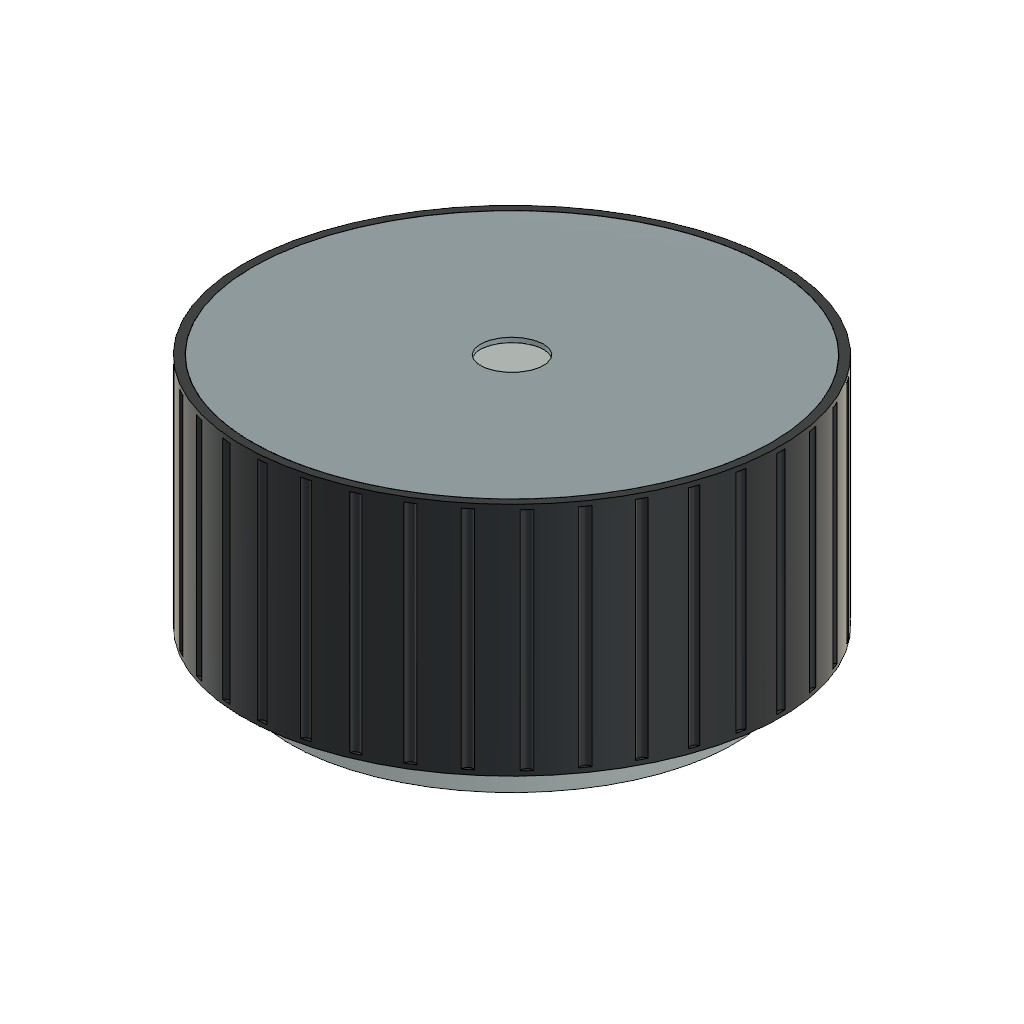
HW17-R0-Fusion (Autodesk Fusion 360 design; units mm, degrees)
description: 12-slot / 14-pole custom brushless haptic wheel. Rotation only. Native Fusion reconstruction of 2026-10-24 R0; concept/prototype, not manufacturing release.
part number: 2026-10-29-11-14-16-184
part number: 2026-10-29-11-14-16-256
part number: 2026-10-29-11-14-16-259
description: POM | 36 shallow axial flutes, max OD17; black matte finish
part number: HW17-R0-01_grip_ring
description: low-carbon magnetic steel; supplier B-H curve required | OD16.4 ID15.4; 0.50 radial wall
part number: HW17-R0-02_rotor_back_iron
description: 6061-T6 aluminium | Spigot adhesive joint; shaft hub controls inner-ring spacing. Final fits by bearing supplier.
part number: HW17-R0-03_rotor_cap
description: Nonmagnetic austenitic stainless steel | D2 precision ground seats; integral lower D2.6 thrust collar, magnet bond face
part number: HW17-R0-04_rotor_shaft
description: N35SH sintered NdFeB, 14 custom radially magnetized arc segments; alternate inward N/S; epoxy protective coating | Pole label is the inward-facing surface; 0.6 degree adhesive joint; independent arcs form a 14-pole ring
part number: HW17-R0-05_magnet_01_N
part number: HW17-R0-05_magnet_02_S
part number: HW17-R0-05_magnet_03_N
part number: HW17-R0-05_magnet_04_S
part number: HW17-R0-05_magnet_05_N
part number: HW17-R0-05_magnet_06_S
part number: HW17-R0-05_magnet_07_N
part number: HW17-R0-05_magnet_08_S
part number: HW17-R0-05_magnet_09_N
part number: HW17-R0-05_magnet_10_S
part number: HW17-R0-05_magnet_11_N
part number: HW17-R0-05_magnet_12_S
part number: HW17-R0-05_magnet_13_N
part number: HW17-R0-05_magnet_14_S
description: 6061-T6 aluminium | Three M1.4 blind pilot holes, bearing fits and adhesive retention require tolerance review
part number: HW17-R0-06_stator_carrier
description: 0.20 mm insulated non-oriented electrical steel, supplier to provide B-H and loss curves | 20 nominal 0.20 mm insulated laminations; final assembled stack 4.00 mm incl. coating
part number: HW17-R0-07_stator_stack
description: Enamelled copper winding envelope | A+, 32 turns D0.13 Cu, finished OD <=0.145, 11/11/10 layers. Envelope is not solid copper.
part number: HW17-R0-08_coil_01_Ap
description: Enamelled copper winding envelope | A-, 32 turns D0.13 Cu, finished OD <=0.145, 11/11/10 layers. Envelope is not solid copper.
part number: HW17-R0-08_coil_02_An
description: Enamelled copper winding envelope | B-, 32 turns D0.13 Cu, finished OD <=0.145, 11/11/10 layers. Envelope is not solid copper.
part number: HW17-R0-08_coil_03_Bn
description: Enamelled copper winding envelope | B+, 32 turns D0.13 Cu, finished OD <=0.145, 11/11/10 layers. Envelope is not solid copper.
part number: HW17-R0-08_coil_04_Bp
description: Enamelled copper winding envelope | C+, 32 turns D0.13 Cu, finished OD <=0.145, 11/11/10 layers. Envelope is not solid copper.
part number: HW17-R0-08_coil_05_Cp
description: Enamelled copper winding envelope | C-, 32 turns D0.13 Cu, finished OD <=0.145, 11/11/10 layers. Envelope is not solid copper.
part number: HW17-R0-08_coil_06_Cn
part number: HW17-R0-08_coil_07_An
part number: HW17-R0-08_coil_08_Ap
part number: HW17-R0-08_coil_09_Bp
part number: HW17-R0-08_coil_10_Bn
part number: HW17-R0-08_coil_11_Cn
part number: HW17-R0-08_coil_12_Cp
description: EZO MR52ZZ 2 x 5 x 2.5 | Envelope only, rolling elements not modelled; zero interference fit in nominal geometry
part number: HW17-R0-09_bearing_1
part number: HW17-R0-09_bearing_2
description: Ground nonmagnetic stainless shim | Match inner/outer spacing to avoid unintended preload; select shim after measurement
part number: HW17-R0-10_inner_spacer
description: Nonmagnetic stainless steel | Bonded outer-race retainer; no contact with inner ring or shields outside outer-ring land
part number: HW17-R0-11_lower_outer_retainer
part number: HW17-R0-12_upper_outer_retainer
description: NdFeB, diametrically magnetized | Single pole pair; D4 x 0.5; 0.02 adhesive to shaft collar. Non-reference magnet requires field validation.
part number: HW17-R0-13_sensor_magnet
description: Rigid-flex envelope, 0.4 mm central stiffened island | D5.5 sensor island and 1.6 mm tail to module edge; actual PCB layout not included
part number: HW17-R0-14_sensor_flex
description: MT6701QT-STD QFN16 | Maximum 3.1 x 3.1 x 0.8 body plus 0.05 solder allowance
part number: HW17-R0-15_MT6701_max_envelope
description: 0201 capacitor envelope | 100 nF adjacent VDD/GND; land pattern and routing to be designed
part number: HW17-R0-16_sensor_decoupling
Autodesk Fusion 360 part; units mm, degrees
(part 1 of 2)
sketch "Sketch1" plane through (0, 0, 0) normal (0, 0, 1) x (1, 0, 0) in component "01_grip_ring POM 防滑外圈"
  circle A0 centre (0, 0) radius 8.5
  circle A1 centre (0, 0) radius 8.2
  dimension "d50" = 17
  dimension "d51" = 16.4
  measures "d50" diameter of A0
  measures "d51" diameter of A1
extrude "外圈 OD17 ID16.4" add sketch "Sketch1" along normal blind 7.6 from surface at 1.2 makes body 1 in component "01_grip_ring POM 防滑外圈"
sketch "Sketch2" plane through (0, 0, 0) normal (0, 0, 1) x (1, 0, 0) in component "01_grip_ring POM 防滑外圈"
  circle A0 centre (8.56, 0) radius 0.18
  circle A1 centre (8.43, 1.4864) radius 0.18
  circle A2 centre (8.0438, 2.9277) radius 0.18
  circle A3 centre (7.4132, 4.28) radius 0.18
  circle A4 centre (6.5573, 5.5023) radius 0.18
  circle A5 centre (5.5023, 6.5573) radius 0.18
  circle A6 centre (4.28, 7.4132) radius 0.18
  circle A7 centre (2.9277, 8.0438) radius 0.18
  circle A8 centre (1.4864, 8.43) radius 0.18
  circle A9 centre (0, 8.56) radius 0.18
  circle A10 centre (-1.4864, 8.43) radius 0.18
  circle A11 centre (-2.9277, 8.0438) radius 0.18
  circle A12 centre (-4.28, 7.4132) radius 0.18
  circle A13 centre (-5.5023, 6.5573) radius 0.18
  circle A14 centre (-6.5573, 5.5023) radius 0.18
  circle A15 centre (-7.4132, 4.28) radius 0.18
  circle A16 centre (-8.0438, 2.9277) radius 0.18
  circle A17 centre (-8.43, 1.4864) radius 0.18
  circle A18 centre (-8.56, 0) radius 0.18
  circle A19 centre (-8.43, -1.4864) radius 0.18
  circle A20 centre (-8.0438, -2.9277) radius 0.18
  circle A21 centre (-7.4132, -4.28) radius 0.18
  circle A22 centre (-6.5573, -5.5023) radius 0.18
  circle A23 centre (-5.5023, -6.5573) radius 0.18
  circle A24 centre (-4.28, -7.4132) radius 0.18
  circle A25 centre (-2.9277, -8.0438) radius 0.18
  circle A26 centre (-1.4864, -8.43) radius 0.18
  circle A27 centre (0, -8.56) radius 0.18
  circle A28 centre (1.4864, -8.43) radius 0.18
  circle A29 centre (2.9277, -8.0438) radius 0.18
  circle A30 centre (4.28, -7.4132) radius 0.18
  circle A31 centre (5.5023, -6.5573) radius 0.18
  circle A32 centre (6.5573, -5.5023) radius 0.18
  circle A33 centre (7.4132, -4.28) radius 0.18
  circle A34 centre (8.0438, -2.9277) radius 0.18
  circle A35 centre (8.43, -1.4864) radius 0.18
extrude "轴向防滑槽 36x" cut sketch "Sketch2" along normal blind 7.3 from surface at 1.35 bodies 1 in component "01_grip_ring POM 防滑外圈"
sketch "Sketch1 (2)" plane through (0, 0, 0) normal (0, 0, 1) x (1, 0, 0) in component "02_rotor_back_iron 低碳钢磁轭"
  circle A0 centre (0, 0) radius 8.2
  circle A1 centre (0, 0) radius 7.7
  dimension "d58" = 16.4
  dimension "d59" = 15.4
  measures "d58" diameter of A0
  measures "d59" diameter of A1
extrude "磁轭 0.50mm 径向壁厚" add sketch "Sketch1 (2)" along normal blind 6.8 from surface at 1.2 separate body makes body 2 in component "02_rotor_back_iron 低碳钢磁轭"
sketch "Sketch1 (3)" plane through (0, 0, 0) normal (0, 0, 1) x (1, 0, 0) in component "03_rotor_cap 铝端盖"
  circle A0 centre (0, 0) radius 8.2
  circle A1 centre (0, 0) radius 1
  dimension "d63" = 16.4
  dimension "d64" = 2
  measures "d63" diameter of A0
  measures "d64" diameter of A1
extrude "端盖" add sketch "Sketch1 (3)" along normal blind 0.8 from surface at 8 separate body makes body 3 in component "03_rotor_cap 铝端盖"
sketch "Sketch2 (2)" plane through (0, 0, 0) normal (0, 0, 1) x (1, 0, 0) in component "03_rotor_cap 铝端盖"
  circle A0 centre (0, 0) radius 7.68
  circle A1 centre (0, 0) radius 7
  dimension "d68" = 15.36
  dimension "d69" = 14
  measures "d68" diameter of A0
  measures "d69" diameter of A1
extrude "胶接定位止口" add sketch "Sketch2 (2)" along normal blind 0.6 from surface at 7.4 bodies 3 in component "03_rotor_cap 铝端盖"
sketch "Sketch3" plane through (0, 0, 0) normal (0, 0, 1) x (1, 0, 0) in component "03_rotor_cap 铝端盖"
  circle A0 centre (0, 0) radius 1.3
  circle A1 centre (0, 0) radius 1
  dimension "d73" = 2.6
  dimension "d74" = 2
  measures "d73" diameter of A0
  measures "d74" diameter of A1
extrude "轴承内圈压肩" add sketch "Sketch3" along normal blind 0.2 from surface at 7.8 bodies 3 in component "03_rotor_cap 铝端盖"
sketch "Sketch4" plane through (0, 0, 0) normal (0, 0, 1) x (1, 0, 0) in component "03_rotor_cap 铝端盖"
  circle A0 centre (0, 0) radius 3.2
  circle A1 centre (0, 0) radius 1.4
extrude "上挡环避让" cut sketch "Sketch4" along normal blind 0.31 from surface at 7.79 bodies 3 in component "03_rotor_cap 铝端盖"
sketch "Sketch1 (4)" plane through (0, 0, 0) normal (0, 0, 1) x (1, 0, 0) in component "04_rotor_shaft 非磁性精密轴 D2"
  circle A0 centre (0, 0) radius 1
  dimension "d81" = 2
  measures "d81" diameter of A0
extrude "轴身" add sketch "Sketch1 (4)" along normal blind 5.95 from surface at 2.7 separate body makes body 4 in component "04_rotor_shaft 非磁性精密轴 D2"
sketch "Sketch2 (3)" plane through (0, 0, 0) normal (0, 0, 1) x (1, 0, 0) in component "04_rotor_shaft 非磁性精密轴 D2"
  circle A0 centre (0, 0) radius 1.3
  dimension "d85" = 2.6
  measures "d85" diameter of A0
extrude "轴底肩" add sketch "Sketch2 (3)" along normal blind 0.3 from surface at 2.4 bodies 4 in component "04_rotor_shaft 非磁性精密轴 D2"
sketch "Sketch1 (5)" plane through (0, 0, 0) normal (0, 0, 1) x (1, 0, 0) in component "05_magnet_01_N 弧形磁钢 内侧N极"
  arc A0 (7.467, -1.6632) -> (7.467, 1.6632) centre (0, 0) ccw
  arc A1 (6.5885, -1.4675) -> (6.5885, 1.4675) centre (0, 0) ccw
  line L0 (7.467, -1.6632) -> (6.5885, -1.4675)
  line L1 (7.467, 1.6632) -> (6.5885, 1.4675)
extrude "径向充磁 N35SH" add sketch "Sketch1 (5)" along normal blind 4.5 from surface at 2.05 separate body makes body 5 in component "05_magnet_01_N 弧形磁钢 内侧N极"
sketch "Sketch1 (6)" plane through (0, 0, 0) normal (0, 0, 1) x (1, 0, 0) in component "05_magnet_02_S 弧形磁钢 内侧S极"
  arc A0 (7.4492, 1.7413) -> (6.0059, 4.7383) centre (0, 0) ccw
  arc A1 (6.5728, 1.5365) -> (5.2993, 4.1809) centre (0, 0) ccw
  line L0 (7.4492, 1.7413) -> (6.5728, 1.5365)
  line L1 (6.0059, 4.7383) -> (5.2993, 4.1809)
extrude "径向充磁 N35SH'" add sketch "Sketch1 (6)" along normal blind 4.5 from surface at 2.05 separate body makes body 6 in component "05_magnet_02_S 弧形磁钢 内侧S极"
sketch "Sketch1 (7)" plane through (0, 0, 0) normal (0, 0, 1) x (1, 0, 0) in component "05_magnet_03_N 弧形磁钢 内侧N极"
  arc A0 (5.956, 4.8009) -> (3.3553, 6.8749) centre (0, 0) ccw
  arc A1 (5.2553, 4.2361) -> (2.9605, 6.0661) centre (0, 0) ccw
  line L0 (5.956, 4.8009) -> (5.2553, 4.2361)
  line L1 (3.3553, 6.8749) -> (2.9605, 6.0661)
extrude "径向充磁 N35SH''" add sketch "Sketch1 (7)" along normal blind 4.5 from surface at 2.05 separate body makes body 7 in component "05_magnet_03_N 弧形磁钢 内侧N极"
sketch "Sketch1 (8)" plane through (0, 0, 0) normal (0, 0, 1) x (1, 0, 0) in component "05_magnet_04_S 弧形磁钢 内侧S极"
  arc A0 (3.2831, 6.9097) -> (0.0401, 7.6499) centre (0, 0) ccw
  arc A1 (2.8968, 6.0968) -> (0.0353, 6.7499) centre (0, 0) ccw
  line L0 (3.2831, 6.9097) -> (2.8968, 6.0968)
  line L1 (0.0401, 7.6499) -> (0.0353, 6.7499)
extrude "径向充磁 N35SH'''" add sketch "Sketch1 (8)" along normal blind 4.5 from surface at 2.05 separate body makes body 8 in component "05_magnet_04_S 弧形磁钢 内侧S极"
sketch "Sketch1 (9)" plane through (0, 0, 0) normal (0, 0, 1) x (1, 0, 0) in component "05_magnet_05_N 弧形磁钢 内侧N极"
  arc A0 (-0.0401, 7.6499) -> (-3.2831, 6.9097) centre (0, 0) ccw
  arc A1 (-0.0353, 6.7499) -> (-2.8968, 6.0968) centre (0, 0) ccw
  line L0 (-0.0401, 7.6499) -> (-0.0353, 6.7499)
  line L1 (-3.2831, 6.9097) -> (-2.8968, 6.0968)
extrude "径向充磁 N35SH''''" add sketch "Sketch1 (9)" along normal blind 4.5 from surface at 2.05 separate body makes body 9 in component "05_magnet_05_N 弧形磁钢 内侧N极"
sketch "Sketch1 (10)" plane through (0, 0, 0) normal (0, 0, 1) x (1, 0, 0) in component "05_magnet_06_S 弧形磁钢 内侧S极"
  arc A0 (-3.3553, 6.8749) -> (-5.956, 4.8009) centre (0, 0) ccw
  arc A1 (-2.9605, 6.0661) -> (-5.2553, 4.2361) centre (0, 0) ccw
  line L0 (-3.3553, 6.8749) -> (-2.9605, 6.0661)
  line L1 (-5.956, 4.8009) -> (-5.2553, 4.2361)
extrude "径向充磁 N35SH'''''" add sketch "Sketch1 (10)" along normal blind 4.5 from surface at 2.05 separate body makes body 10 in component "05_magnet_06_S 弧形磁钢 内侧S极"
sketch "Sketch1 (11)" plane through (0, 0, 0) normal (0, 0, 1) x (1, 0, 0) in component "05_magnet_07_N 弧形磁钢 内侧N极"
  arc A0 (-6.0059, 4.7383) -> (-7.4492, 1.7413) centre (0, 0) ccw
  arc A1 (-5.2993, 4.1809) -> (-6.5728, 1.5365) centre (0, 0) ccw
  line L0 (-6.0059, 4.7383) -> (-5.2993, 4.1809)
  line L1 (-7.4492, 1.7413) -> (-6.5728, 1.5365)
extrude "径向充磁 N35SH''''''" add sketch "Sketch1 (11)" along normal blind 4.5 from surface at 2.05 separate body makes body 11 in component "05_magnet_07_N 弧形磁钢 内侧N极"
sketch "Sketch1 (12)" plane through (0, 0, 0) normal (0, 0, 1) x (1, 0, 0) in component "05_magnet_08_S 弧形磁钢 内侧S极"
  arc A0 (-7.467, 1.6632) -> (-7.467, -1.6632) centre (0, 0) ccw
  arc A1 (-6.5885, 1.4675) -> (-6.5885, -1.4675) centre (0, 0) ccw
  line L0 (-7.467, 1.6632) -> (-6.5885, 1.4675)
  line L1 (-7.467, -1.6632) -> (-6.5885, -1.4675)
extrude "径向充磁 N35SH'''''''" add sketch "Sketch1 (12)" along normal blind 4.5 from surface at 2.05 separate body makes body 12 in component "05_magnet_08_S 弧形磁钢 内侧S极"
sketch "Sketch1 (13)" plane through (0, 0, 0) normal (0, 0, 1) x (1, 0, 0) in component "05_magnet_09_N 弧形磁钢 内侧N极"
  arc A0 (-7.4492, -1.7413) -> (-6.0059, -4.7383) centre (0, 0) ccw
  arc A1 (-6.5728, -1.5365) -> (-5.2993, -4.1809) centre (0, 0) ccw
  line L0 (-7.4492, -1.7413) -> (-6.5728, -1.5365)
  line L1 (-6.0059, -4.7383) -> (-5.2993, -4.1809)
extrude "径向充磁 N35SH''''''''" add sketch "Sketch1 (13)" along normal blind 4.5 from surface at 2.05 separate body makes body 13 in component "05_magnet_09_N 弧形磁钢 内侧N极"
sketch "Sketch1 (14)" plane through (0, 0, 0) normal (0, 0, 1) x (1, 0, 0) in component "05_magnet_10_S 弧形磁钢 内侧S极"
  arc A0 (-5.956, -4.8009) -> (-3.3553, -6.8749) centre (0, 0) ccw
  arc A1 (-5.2553, -4.2361) -> (-2.9605, -6.0661) centre (0, 0) ccw
  line L0 (-5.956, -4.8009) -> (-5.2553, -4.2361)
  line L1 (-3.3553, -6.8749) -> (-2.9605, -6.0661)
extrude "径向充磁 N35SH'''''''''" add sketch "Sketch1 (14)" along normal blind 4.5 from surface at 2.05 separate body makes body 14 in component "05_magnet_10_S 弧形磁钢 内侧S极"
sketch "Sketch1 (15)" plane through (0, 0, 0) normal (0, 0, 1) x (1, 0, 0) in component "05_magnet_11_N 弧形磁钢 内侧N极"
  arc A0 (-3.2831, -6.9097) -> (-0.0401, -7.6499) centre (0, 0) ccw
  arc A1 (-2.8968, -6.0968) -> (-0.0353, -6.7499) centre (0, 0) ccw
  line L0 (-3.2831, -6.9097) -> (-2.8968, -6.0968)
  line L1 (-0.0401, -7.6499) -> (-0.0353, -6.7499)
extrude "径向充磁 N35SH''''''''''" add sketch "Sketch1 (15)" along normal blind 4.5 from surface at 2.05 separate body makes body 15 in component "05_magnet_11_N 弧形磁钢 内侧N极"
sketch "Sketch1 (16)" plane through (0, 0, 0) normal (0, 0, 1) x (1, 0, 0) in component "05_magnet_12_S 弧形磁钢 内侧S极"
  arc A0 (0.0401, -7.6499) -> (3.2831, -6.9097) centre (0, 0) ccw
  arc A1 (0.0353, -6.7499) -> (2.8968, -6.0968) centre (0, 0) ccw
  line L0 (0.0401, -7.6499) -> (0.0353, -6.7499)
  line L1 (3.2831, -6.9097) -> (2.8968, -6.0968)
extrude "径向充磁 N35SH'''''''''''" add sketch "Sketch1 (16)" along normal blind 4.5 from surface at 2.05 separate body makes body 16 in component "05_magnet_12_S 弧形磁钢 内侧S极"
sketch "Sketch1 (17)" plane through (0, 0, 0) normal (0, 0, 1) x (1, 0, 0) in component "05_magnet_13_N 弧形磁钢 内侧N极"
  arc A0 (3.3553, -6.8749) -> (5.956, -4.8009) centre (0, 0) ccw
  arc A1 (2.9605, -6.0661) -> (5.2553, -4.2361) centre (0, 0) ccw
  line L0 (3.3553, -6.8749) -> (2.9605, -6.0661)
  line L1 (5.956, -4.8009) -> (5.2553, -4.2361)
extrude "径向充磁 N35SH''''''''''''" add sketch "Sketch1 (17)" along normal blind 4.5 from surface at 2.05 separate body makes body 17 in component "05_magnet_13_N 弧形磁钢 内侧N极"
sketch "Sketch1 (18)" plane through (0, 0, 0) normal (0, 0, 1) x (1, 0, 0) in component "05_magnet_14_S 弧形磁钢 内侧S极"
  arc A0 (6.0059, -4.7383) -> (7.4492, -1.7413) centre (0, 0) ccw
  arc A1 (5.2993, -4.1809) -> (6.5728, -1.5365) centre (0, 0) ccw
  line L0 (6.0059, -4.7383) -> (5.2993, -4.1809)
  line L1 (7.4492, -1.7413) -> (6.5728, -1.5365)
extrude "径向充磁 N35SH'''''''''''''" add sketch "Sketch1 (18)" along normal blind 4.5 from surface at 2.05 separate body makes body 18 in component "05_magnet_14_S 弧形磁钢 内侧S极"
sketch "Sketch1 (19)" plane through (0, 0, 0) normal (0, 0, 1) x (1, 0, 0) in component "06_stator_carrier 铝固定座"
  circle A0 centre (0, 0) radius 7
  dimension "d131" = 14
  measures "d131" diameter of A0
extrude "安装底盘" add sketch "Sketch1 (19)" along normal blind 0.6 separate body makes body 19 in component "06_stator_carrier 铝固定座"
sketch "Sketch2 (4)" plane through (0, 0, 0) normal (0, 0, 1) x (1, 0, 0) in component "06_stator_carrier 铝固定座"
  circle A0 centre (0, 0) radius 2.8
  dimension "d135" = 5.6
  measures "d135" diameter of A0
extrude "传感器板沉腔" cut sketch "Sketch2 (4)" along normal blind 0.41 from surface at -0.01 bodies 19 in component "06_stator_carrier 铝固定座"
sketch "Sketch3 (2)" plane through (0, 0, 0) normal (0, 0, 1) x (1, 0, 0) in component "06_stator_carrier 铝固定座"
  circle A0 centre (0, 0) radius 2.5
  dimension "d139" = 5
  measures "d139" diameter of A0
extrude "中心通腔" cut sketch "Sketch3 (2)" along normal blind 0.21 from surface at 0.4 bodies 19 in component "06_stator_carrier 铝固定座"
sketch "Sketch4 (2)" plane through (0, 0, 0) normal (0, 0, 1) x (1, 0, 0) in component "06_stator_carrier 铝固定座"
  circle A0 centre (0, 0) radius 3
  circle A1 centre (0, 0) radius 2.5
  dimension "d143" = 6
  dimension "d144" = 5
  measures "d143" diameter of A0
  measures "d144" diameter of A1
extrude "轴承座筒" add sketch "Sketch4 (2)" along normal blind 7.2 from surface at 0.6 bodies 19 in component "06_stator_carrier 铝固定座"
sketch "Sketch5" plane through (0, 0, 0) normal (0, 0, 1) x (1, 0, 0) in component "06_stator_carrier 铝固定座"
  circle A0 centre (0, 0) radius 2.5
  circle A1 centre (0, 0) radius 2.25
  dimension "d148" = 5
  dimension "d149" = 4.5
  measures "d148" diameter of A0
  measures "d149" diameter of A1
extrude "轴承外圈间隔肩" add sketch "Sketch5" along normal blind 0.1 from surface at 5.2 bodies 19 in component "06_stator_carrier 铝固定座"
sketch "Sketch6" plane through (0, 0, 0) normal (0, 0, 1) x (1, 0, 0) in component "06_stator_carrier 铝固定座"
  circle A0 centre (4.6765, 2.7) radius 1.2
  dimension "d153" = 2.4
  measures "d153" diameter of A0
extrude "安装凸台 1" add sketch "Sketch6" along normal blind 0.9 from surface at 0.6 bodies 19 in component "06_stator_carrier 铝固定座"
sketch "Sketch7" plane through (0, 0, 0) normal (0, 0, 1) x (1, 0, 0) in component "06_stator_carrier 铝固定座"
  circle A0 centre (4.6765, 2.7) radius 0.55
  dimension "d157" = 1.1
  measures "d157" diameter of A0
extrude "M1.4 底孔 1 无牙型" cut sketch "Sketch7" along normal blind 1.26 from surface at -0.01 bodies 19 in component "06_stator_carrier 铝固定座"
sketch "Sketch8" plane through (0, 0, 0) normal (0, 0, 1) x (1, 0, 0) in component "06_stator_carrier 铝固定座"
  circle A0 centre (-4.6765, 2.7) radius 1.2
  dimension "d161" = 2.4
  measures "d161" diameter of A0
extrude "安装凸台 2" add sketch "Sketch8" along normal blind 0.9 from surface at 0.6 bodies 19 in component "06_stator_carrier 铝固定座"
sketch "Sketch9" plane through (0, 0, 0) normal (0, 0, 1) x (1, 0, 0) in component "06_stator_carrier 铝固定座"
  circle A0 centre (-4.6765, 2.7) radius 0.55
  dimension "d165" = 1.1
  measures "d165" diameter of A0
extrude "M1.4 底孔 2 无牙型" cut sketch "Sketch9" along normal blind 1.26 from surface at -0.01 bodies 19 in component "06_stator_carrier 铝固定座"
sketch "Sketch10" plane through (0, 0, 0) normal (0, 0, 1) x (1, 0, 0) in component "06_stator_carrier 铝固定座"
  circle A0 centre (0, -5.4) radius 1.2
  dimension "d169" = 2.4
  measures "d169" diameter of A0
extrude "安装凸台 3" add sketch "Sketch10" along normal blind 0.9 from surface at 0.6 bodies 19 in component "06_stator_carrier 铝固定座"
sketch "Sketch11" plane through (0, 0, 0) normal (0, 0, 1) x (1, 0, 0) in component "06_stator_carrier 铝固定座"
  circle A0 centre (0, -5.4) radius 0.55
  dimension "d173" = 1.1
  measures "d173" diameter of A0
extrude "M1.4 底孔 3 无牙型" cut sketch "Sketch11" along normal blind 1.26 from surface at -0.01 bodies 19 in component "06_stator_carrier 铝固定座"
sketch "Sketch12" plane through (0, 0, 0) normal (0, 0, 1) x (1, 0, 0) in component "06_stator_carrier 铝固定座"
  line L0 (0.7071, 0.7071) -> (-4.3134, 5.7276)
  line L1 (-4.3134, 5.7276) -> (-5.7276, 4.3134)
  line L2 (-5.7276, 4.3134) -> (-0.7071, -0.7071)
  line L3 (-0.7071, -0.7071) -> (0.7071, 0.7071)
extrude "传感器软排线通道 135deg" cut sketch "Sketch12" along normal blind 0.4 bodies 19 in component "06_stator_carrier 铝固定座"
sketch "Sketch13" plane through (0, 0, 0) normal (0, 0, 1) x (1, 0, 0) in component "06_stator_carrier 铝固定座"
  circle A0 centre (0, 4.7) radius 0.45
extrude "相线通孔 D0.9" cut sketch "Sketch13" along normal blind 0.62 from surface at -0.01 bodies 19 in component "06_stator_carrier 铝固定座"
sketch "Sketch1 (20)" plane through (0, 0, 0) normal (0, 0, 1) x (1, 0, 0) in component "07_stator_stack 12 槽叠片铁芯 H4"
  circle A0 centre (0, 0) radius 4
  circle A1 centre (0, 0) radius 3.05
  dimension "d183" = 8
  dimension "d184" = 6.1
  measures "d183" diameter of A0
  measures "d184" diameter of A1
extrude "定子背轭" add sketch "Sketch1 (20)" along normal blind 4 from surface at 2.3 separate body makes body 20 in component "07_stator_stack 12 槽叠片铁芯 H4"
sketch "Sketch2 (5)" plane through (0, 0, 0) normal (0, 0, 1) x (1, 0, 0) in component "07_stator_stack 12 槽叠片铁芯 H4"
  line L0 (3.9, -0.4) -> (6.15, -0.4)
  line L1 (6.15, -0.4) -> (6.15, 0.4)
  line L2 (6.15, 0.4) -> (3.9, 0.4)
  line L3 (3.9, 0.4) -> (3.9, -0.4)
extrude "齿 01" add sketch "Sketch2 (5)" along normal blind 4 from surface at 2.3 bodies 20 in component "07_stator_stack 12 槽叠片铁芯 H4"
sketch "Sketch3 (3)" plane through (0, 0, 0) normal (0, 0, 1) x (1, 0, 0) in component "07_stator_stack 12 槽叠片铁芯 H4"
  arc A0 (6.3806, -1.2403) -> (6.3806, 1.2403) centre (0, 0) ccw
  arc A1 (5.9879, -1.1639) -> (5.9879, 1.1639) centre (0, 0) ccw
  line L0 (6.3806, -1.2403) -> (5.9879, -1.1639)
  line L1 (6.3806, 1.2403) -> (5.9879, 1.1639)
extrude "齿靴 01" add sketch "Sketch3 (3)" along normal blind 4 from surface at 2.3 bodies 20 in component "07_stator_stack 12 槽叠片铁芯 H4"
sketch "Sketch4 (3)" plane through (0, 0, 0) normal (0, 0, 1) x (1, 0, 0) in component "07_stator_stack 12 槽叠片铁芯 H4"
  line L0 (3.5775, 1.6036) -> (5.5261, 2.7286)
  line L1 (5.5261, 2.7286) -> (5.1261, 3.4214)
  line L2 (5.1261, 3.4214) -> (3.1775, 2.2964)
  line L3 (3.1775, 2.2964) -> (3.5775, 1.6036)
extrude "齿 02" add sketch "Sketch4 (3)" along normal blind 4 from surface at 2.3 bodies 20 in component "07_stator_stack 12 槽叠片铁芯 H4"
sketch "Sketch5 (2)" plane through (0, 0, 0) normal (0, 0, 1) x (1, 0, 0) in component "07_stator_stack 12 槽叠片铁芯 H4"
  arc A0 (6.1459, 2.1162) -> (4.9056, 4.2644) centre (0, 0) ccw
  arc A1 (5.7677, 1.986) -> (4.6037, 4.002) centre (0, 0) ccw
  line L0 (6.1459, 2.1162) -> (5.7677, 1.986)
  line L1 (4.9056, 4.2644) -> (4.6037, 4.002)
extrude "齿靴 02" add sketch "Sketch5 (2)" along normal blind 4 from surface at 2.3 bodies 20 in component "07_stator_stack 12 槽叠片铁芯 H4"
sketch "Sketch6 (2)" plane through (0, 0, 0) normal (0, 0, 1) x (1, 0, 0) in component "07_stator_stack 12 槽叠片铁芯 H4"
  line L0 (2.2964, 3.1775) -> (3.4214, 5.1261)
  line L1 (3.4214, 5.1261) -> (2.7286, 5.5261)
  line L2 (2.7286, 5.5261) -> (1.6036, 3.5775)
  line L3 (1.6036, 3.5775) -> (2.2964, 3.1775)
extrude "齿 03" add sketch "Sketch6 (2)" along normal blind 4 from surface at 2.3 bodies 20 in component "07_stator_stack 12 槽叠片铁芯 H4"
sketch "Sketch7 (2)" plane through (0, 0, 0) normal (0, 0, 1) x (1, 0, 0) in component "07_stator_stack 12 槽叠片铁芯 H4"
  arc A0 (4.2644, 4.9056) -> (2.1162, 6.1459) centre (0, 0) ccw
  arc A1 (4.002, 4.6037) -> (1.986, 5.7677) centre (0, 0) ccw
  line L0 (4.2644, 4.9056) -> (4.002, 4.6037)
  line L1 (2.1162, 6.1459) -> (1.986, 5.7677)
extrude "齿靴 03" add sketch "Sketch7 (2)" along normal blind 4 from surface at 2.3 bodies 20 in component "07_stator_stack 12 槽叠片铁芯 H4"
sketch "Sketch8 (2)" plane through (0, 0, 0) normal (0, 0, 1) x (1, 0, 0) in component "07_stator_stack 12 槽叠片铁芯 H4"
  line L0 (0.4, 3.9) -> (0.4, 6.15)
  line L1 (0.4, 6.15) -> (-0.4, 6.15)
  line L2 (-0.4, 6.15) -> (-0.4, 3.9)
  line L3 (-0.4, 3.9) -> (0.4, 3.9)
extrude "齿 04" add sketch "Sketch8 (2)" along normal blind 4 from surface at 2.3 bodies 20 in component "07_stator_stack 12 槽叠片铁芯 H4"
sketch "Sketch9 (2)" plane through (0, 0, 0) normal (0, 0, 1) x (1, 0, 0) in component "07_stator_stack 12 槽叠片铁芯 H4"
  arc A0 (1.2403, 6.3806) -> (-1.2403, 6.3806) centre (0, 0) ccw
  arc A1 (1.1639, 5.9879) -> (-1.1639, 5.9879) centre (0, 0) ccw
  line L0 (1.2403, 6.3806) -> (1.1639, 5.9879)
  line L1 (-1.2403, 6.3806) -> (-1.1639, 5.9879)
extrude "齿靴 04" add sketch "Sketch9 (2)" along normal blind 4 from surface at 2.3 bodies 20 in component "07_stator_stack 12 槽叠片铁芯 H4"
sketch "Sketch10 (2)" plane through (0, 0, 0) normal (0, 0, 1) x (1, 0, 0) in component "07_stator_stack 12 槽叠片铁芯 H4"
  line L0 (-1.6036, 3.5775) -> (-2.7286, 5.5261)
  line L1 (-2.7286, 5.5261) -> (-3.4214, 5.1261)
  line L2 (-3.4214, 5.1261) -> (-2.2964, 3.1775)
  line L3 (-2.2964, 3.1775) -> (-1.6036, 3.5775)
extrude "齿 05" add sketch "Sketch10 (2)" along normal blind 4 from surface at 2.3 bodies 20 in component "07_stator_stack 12 槽叠片铁芯 H4"
sketch "Sketch11 (2)" plane through (0, 0, 0) normal (0, 0, 1) x (1, 0, 0) in component "07_stator_stack 12 槽叠片铁芯 H4"
  arc A0 (-2.1162, 6.1459) -> (-4.2644, 4.9056) centre (0, 0) ccw
  arc A1 (-1.986, 5.7677) -> (-4.002, 4.6037) centre (0, 0) ccw
  line L0 (-2.1162, 6.1459) -> (-1.986, 5.7677)
  line L1 (-4.2644, 4.9056) -> (-4.002, 4.6037)
extrude "齿靴 05" add sketch "Sketch11 (2)" along normal blind 4 from surface at 2.3 bodies 20 in component "07_stator_stack 12 槽叠片铁芯 H4"
sketch "Sketch12 (2)" plane through (0, 0, 0) normal (0, 0, 1) x (1, 0, 0) in component "07_stator_stack 12 槽叠片铁芯 H4"
  line L0 (-3.1775, 2.2964) -> (-5.1261, 3.4214)
  line L1 (-5.1261, 3.4214) -> (-5.5261, 2.7286)
  line L2 (-5.5261, 2.7286) -> (-3.5775, 1.6036)
  line L3 (-3.5775, 1.6036) -> (-3.1775, 2.2964)
extrude "齿 06" add sketch "Sketch12 (2)" along normal blind 4 from surface at 2.3 bodies 20 in component "07_stator_stack 12 槽叠片铁芯 H4"
sketch "Sketch13 (2)" plane through (0, 0, 0) normal (0, 0, 1) x (1, 0, 0) in component "07_stator_stack 12 槽叠片铁芯 H4"
  arc A0 (-4.9056, 4.2644) -> (-6.1459, 2.1162) centre (0, 0) ccw
  arc A1 (-4.6037, 4.002) -> (-5.7677, 1.986) centre (0, 0) ccw
  line L0 (-4.9056, 4.2644) -> (-4.6037, 4.002)
  line L1 (-6.1459, 2.1162) -> (-5.7677, 1.986)
extrude "齿靴 06" add sketch "Sketch13 (2)" along normal blind 4 from surface at 2.3 bodies 20 in component "07_stator_stack 12 槽叠片铁芯 H4"
sketch "Sketch14" plane through (0, 0, 0) normal (0, 0, 1) x (1, 0, 0) in component "07_stator_stack 12 槽叠片铁芯 H4"
  line L0 (-3.9, 0.4) -> (-6.15, 0.4)
  line L1 (-6.15, 0.4) -> (-6.15, -0.4)
  line L2 (-6.15, -0.4) -> (-3.9, -0.4)
  line L3 (-3.9, -0.4) -> (-3.9, 0.4)
extrude "齿 07" add sketch "Sketch14" along normal blind 4 from surface at 2.3 bodies 20 in component "07_stator_stack 12 槽叠片铁芯 H4"
sketch "Sketch15" plane through (0, 0, 0) normal (0, 0, 1) x (1, 0, 0) in component "07_stator_stack 12 槽叠片铁芯 H4"
  arc A0 (-6.3806, 1.2403) -> (-6.3806, -1.2403) centre (0, 0) ccw
  arc A1 (-5.9879, 1.1639) -> (-5.9879, -1.1639) centre (0, 0) ccw
  line L0 (-6.3806, 1.2403) -> (-5.9879, 1.1639)
  line L1 (-6.3806, -1.2403) -> (-5.9879, -1.1639)
extrude "齿靴 07" add sketch "Sketch15" along normal blind 4 from surface at 2.3 bodies 20 in component "07_stator_stack 12 槽叠片铁芯 H4"
sketch "Sketch16" plane through (0, 0, 0) normal (0, 0, 1) x (1, 0, 0) in component "07_stator_stack 12 槽叠片铁芯 H4"
  line L0 (-3.5775, -1.6036) -> (-5.5261, -2.7286)
  line L1 (-5.5261, -2.7286) -> (-5.1261, -3.4214)
  line L2 (-5.1261, -3.4214) -> (-3.1775, -2.2964)
  line L3 (-3.1775, -2.2964) -> (-3.5775, -1.6036)
extrude "齿 08" add sketch "Sketch16" along normal blind 4 from surface at 2.3 bodies 20 in component "07_stator_stack 12 槽叠片铁芯 H4"
sketch "Sketch17" plane through (0, 0, 0) normal (0, 0, 1) x (1, 0, 0) in component "07_stator_stack 12 槽叠片铁芯 H4"
  arc A0 (-6.1459, -2.1162) -> (-4.9056, -4.2644) centre (0, 0) ccw
  arc A1 (-5.7677, -1.986) -> (-4.6037, -4.002) centre (0, 0) ccw
  line L0 (-6.1459, -2.1162) -> (-5.7677, -1.986)
  line L1 (-4.9056, -4.2644) -> (-4.6037, -4.002)
extrude "齿靴 08" add sketch "Sketch17" along normal blind 4 from surface at 2.3 bodies 20 in component "07_stator_stack 12 槽叠片铁芯 H4"
sketch "Sketch18" plane through (0, 0, 0) normal (0, 0, 1) x (1, 0, 0) in component "07_stator_stack 12 槽叠片铁芯 H4"
  line L0 (-2.2964, -3.1775) -> (-3.4214, -5.1261)
  line L1 (-3.4214, -5.1261) -> (-2.7286, -5.5261)
  line L2 (-2.7286, -5.5261) -> (-1.6036, -3.5775)
  line L3 (-1.6036, -3.5775) -> (-2.2964, -3.1775)
extrude "齿 09" add sketch "Sketch18" along normal blind 4 from surface at 2.3 bodies 20 in component "07_stator_stack 12 槽叠片铁芯 H4"
sketch "Sketch19" plane through (0, 0, 0) normal (0, 0, 1) x (1, 0, 0) in component "07_stator_stack 12 槽叠片铁芯 H4"
  arc A0 (-4.2644, -4.9056) -> (-2.1162, -6.1459) centre (0, 0) ccw
  arc A1 (-4.002, -4.6037) -> (-1.986, -5.7677) centre (0, 0) ccw
  line L0 (-4.2644, -4.9056) -> (-4.002, -4.6037)
  line L1 (-2.1162, -6.1459) -> (-1.986, -5.7677)
extrude "齿靴 09" add sketch "Sketch19" along normal blind 4 from surface at 2.3 bodies 20 in component "07_stator_stack 12 槽叠片铁芯 H4"
sketch "Sketch20" plane through (0, 0, 0) normal (0, 0, 1) x (1, 0, 0) in component "07_stator_stack 12 槽叠片铁芯 H4"
  line L0 (-0.4, -3.9) -> (-0.4, -6.15)
  line L1 (-0.4, -6.15) -> (0.4, -6.15)
  line L2 (0.4, -6.15) -> (0.4, -3.9)
  line L3 (0.4, -3.9) -> (-0.4, -3.9)
extrude "齿 10" add sketch "Sketch20" along normal blind 4 from surface at 2.3 bodies 20 in component "07_stator_stack 12 槽叠片铁芯 H4"
sketch "Sketch21" plane through (0, 0, 0) normal (0, 0, 1) x (1, 0, 0) in component "07_stator_stack 12 槽叠片铁芯 H4"
  arc A0 (-1.2403, -6.3806) -> (1.2403, -6.3806) centre (0, 0) ccw
  arc A1 (-1.1639, -5.9879) -> (1.1639, -5.9879) centre (0, 0) ccw
  line L0 (-1.2403, -6.3806) -> (-1.1639, -5.9879)
  line L1 (1.2403, -6.3806) -> (1.1639, -5.9879)
extrude "齿靴 10" add sketch "Sketch21" along normal blind 4 from surface at 2.3 bodies 20 in component "07_stator_stack 12 槽叠片铁芯 H4"
sketch "Sketch22" plane through (0, 0, 0) normal (0, 0, 1) x (1, 0, 0) in component "07_stator_stack 12 槽叠片铁芯 H4"
  line L0 (1.6036, -3.5775) -> (2.7286, -5.5261)
  line L1 (2.7286, -5.5261) -> (3.4214, -5.1261)
  line L2 (3.4214, -5.1261) -> (2.2964, -3.1775)
  line L3 (2.2964, -3.1775) -> (1.6036, -3.5775)
extrude "齿 11" add sketch "Sketch22" along normal blind 4 from surface at 2.3 bodies 20 in component "07_stator_stack 12 槽叠片铁芯 H4"
sketch "Sketch23" plane through (0, 0, 0) normal (0, 0, 1) x (1, 0, 0) in component "07_stator_stack 12 槽叠片铁芯 H4"
  arc A0 (2.1162, -6.1459) -> (4.2644, -4.9056) centre (0, 0) ccw
  arc A1 (1.986, -5.7677) -> (4.002, -4.6037) centre (0, 0) ccw
  line L0 (2.1162, -6.1459) -> (1.986, -5.7677)
  line L1 (4.2644, -4.9056) -> (4.002, -4.6037)
extrude "齿靴 11" add sketch "Sketch23" along normal blind 4 from surface at 2.3 bodies 20 in component "07_stator_stack 12 槽叠片铁芯 H4"
sketch "Sketch24" plane through (0, 0, 0) normal (0, 0, 1) x (1, 0, 0) in component "07_stator_stack 12 槽叠片铁芯 H4"
  line L0 (3.1775, -2.2964) -> (5.1261, -3.4214)
  line L1 (5.1261, -3.4214) -> (5.5261, -2.7286)
  line L2 (5.5261, -2.7286) -> (3.5775, -1.6036)
  line L3 (3.5775, -1.6036) -> (3.1775, -2.2964)
extrude "齿 12" add sketch "Sketch24" along normal blind 4 from surface at 2.3 bodies 20 in component "07_stator_stack 12 槽叠片铁芯 H4"
sketch "Sketch25" plane through (0, 0, 0) normal (0, 0, 1) x (1, 0, 0) in component "07_stator_stack 12 槽叠片铁芯 H4"
  arc A0 (4.9056, -4.2644) -> (6.1459, -2.1162) centre (0, 0) ccw
  arc A1 (4.6037, -4.002) -> (5.7677, -1.986) centre (0, 0) ccw
  line L0 (4.9056, -4.2644) -> (4.6037, -4.002)
  line L1 (6.1459, -2.1162) -> (5.7677, -1.986)
extrude "齿靴 12" add sketch "Sketch25" along normal blind 4 from surface at 2.3 bodies 20 in component "07_stator_stack 12 槽叠片铁芯 H4"
sketch "Sketch1 (21)" plane through (0, 0, 0) normal (0, 0, 1) x (1, 0, 0) in component "08_coil_01_Ap Ap 32匝绕组包络"
  line L0 (4.2, -0.98) -> (5.95, -0.98)
  line L1 (5.95, -0.98) -> (5.95, 0.98)
  line L2 (5.95, 0.98) -> (4.2, 0.98)
  line L3 (4.2, 0.98) -> (4.2, -0.98)
extrude "线圈外包络" add sketch "Sketch1 (21)" along normal blind 5.16 from surface at 1.72 separate body makes body 21 in component "08_coil_01_Ap Ap 32匝绕组包络"
sketch "Sketch2 (6)" plane through (0, 0, 0) normal (0, 0, 1) x (1, 0, 0) in component "08_coil_01_Ap Ap 32匝绕组包络"
  line L0 (4.19, -0.5) -> (5.96, -0.5)
  line L1 (5.96, -0.5) -> (5.96, 0.5)
  line L2 (5.96, 0.5) -> (4.19, 0.5)
  line L3 (4.19, 0.5) -> (4.19, -0.5)
extrude "绕组齿间通道" cut sketch "Sketch2 (6)" along normal blind 4.2 from surface at 2.2 bodies 21 in component "08_coil_01_Ap Ap 32匝绕组包络"
sketch "Sketch1 (22)" plane through (0, 0, 0) normal (0, 0, 1) x (1, 0, 0) in component "08_coil_02_An An 32匝绕组包络"
  line L0 (4.1273, 1.2513) -> (5.6429, 2.1263)
  line L1 (5.6429, 2.1263) -> (4.6629, 3.8237)
  line L2 (4.6629, 3.8237) -> (3.1473, 2.9487)
  line L3 (3.1473, 2.9487) -> (4.1273, 1.2513)
extrude "线圈外包络'" add sketch "Sketch1 (22)" along normal blind 5.16 from surface at 1.72 separate body makes body 22 in component "08_coil_02_An An 32匝绕组包络"
sketch "Sketch2 (7)" plane through (0, 0, 0) normal (0, 0, 1) x (1, 0, 0) in component "08_coil_02_An An 32匝绕组包络"
  line L0 (3.8786, 1.662) -> (5.4115, 2.547)
  line L1 (5.4115, 2.547) -> (4.9115, 3.413)
  line L2 (4.9115, 3.413) -> (3.3786, 2.528)
  line L3 (3.3786, 2.528) -> (3.8786, 1.662)
extrude "绕组齿间通道'" cut sketch "Sketch2 (7)" along normal blind 4.2 from surface at 2.2 bodies 22 in component "08_coil_02_An An 32匝绕组包络"
sketch "Sketch1 (23)" plane through (0, 0, 0) normal (0, 0, 1) x (1, 0, 0) in component "08_coil_03_Bn Bn 32匝绕组包络"
  line L0 (2.9487, 3.1473) -> (3.8237, 4.6629)
  line L1 (3.8237, 4.6629) -> (2.1263, 5.6429)
  line L2 (2.1263, 5.6429) -> (1.2513, 4.1273)
  line L3 (1.2513, 4.1273) -> (2.9487, 3.1473)
extrude "线圈外包络''" add sketch "Sketch1 (23)" along normal blind 5.16 from surface at 1.72 separate body makes body 23 in component "08_coil_03_Bn Bn 32匝绕组包络"
sketch "Sketch2 (8)" plane through (0, 0, 0) normal (0, 0, 1) x (1, 0, 0) in component "08_coil_03_Bn Bn 32匝绕组包络"
  line L0 (2.528, 3.3786) -> (3.413, 4.9115)
  line L1 (3.413, 4.9115) -> (2.547, 5.4115)
  line L2 (2.547, 5.4115) -> (1.662, 3.8786)
  line L3 (1.662, 3.8786) -> (2.528, 3.3786)
extrude "绕组齿间通道''" cut sketch "Sketch2 (8)" along normal blind 4.2 from surface at 2.2 bodies 23 in component "08_coil_03_Bn Bn 32匝绕组包络"
sketch "Sketch1 (24)" plane through (0, 0, 0) normal (0, 0, 1) x (1, 0, 0) in component "08_coil_04_Bp Bp 32匝绕组包络"
  line L0 (0.98, 4.2) -> (0.98, 5.95)
  line L1 (0.98, 5.95) -> (-0.98, 5.95)
  line L2 (-0.98, 5.95) -> (-0.98, 4.2)
  line L3 (-0.98, 4.2) -> (0.98, 4.2)
extrude "线圈外包络'''" add sketch "Sketch1 (24)" along normal blind 5.16 from surface at 1.72 separate body makes body 24 in component "08_coil_04_Bp Bp 32匝绕组包络"
sketch "Sketch2 (9)" plane through (0, 0, 0) normal (0, 0, 1) x (1, 0, 0) in component "08_coil_04_Bp Bp 32匝绕组包络"
  line L0 (0.5, 4.19) -> (0.5, 5.96)
  line L1 (0.5, 5.96) -> (-0.5, 5.96)
  line L2 (-0.5, 5.96) -> (-0.5, 4.19)
  line L3 (-0.5, 4.19) -> (0.5, 4.19)
extrude "绕组齿间通道'''" cut sketch "Sketch2 (9)" along normal blind 4.2 from surface at 2.2 bodies 24 in component "08_coil_04_Bp Bp 32匝绕组包络"
sketch "Sketch1 (25)" plane through (0, 0, 0) normal (0, 0, 1) x (1, 0, 0) in component "08_coil_05_Cp Cp 32匝绕组包络"
  line L0 (-1.2513, 4.1273) -> (-2.1263, 5.6429)
  line L1 (-2.1263, 5.6429) -> (-3.8237, 4.6629)
  line L2 (-3.8237, 4.6629) -> (-2.9487, 3.1473)
  line L3 (-2.9487, 3.1473) -> (-1.2513, 4.1273)
extrude "线圈外包络''''" add sketch "Sketch1 (25)" along normal blind 5.16 from surface at 1.72 separate body makes body 25 in component "08_coil_05_Cp Cp 32匝绕组包络"
sketch "Sketch2 (10)" plane through (0, 0, 0) normal (0, 0, 1) x (1, 0, 0) in component "08_coil_05_Cp Cp 32匝绕组包络"
  line L0 (-1.662, 3.8786) -> (-2.547, 5.4115)
  line L1 (-2.547, 5.4115) -> (-3.413, 4.9115)
  line L2 (-3.413, 4.9115) -> (-2.528, 3.3786)
  line L3 (-2.528, 3.3786) -> (-1.662, 3.8786)
extrude "绕组齿间通道''''" cut sketch "Sketch2 (10)" along normal blind 4.2 from surface at 2.2 bodies 25 in component "08_coil_05_Cp Cp 32匝绕组包络"
sketch "Sketch1 (26)" plane through (0, 0, 0) normal (0, 0, 1) x (1, 0, 0) in component "08_coil_06_Cn Cn 32匝绕组包络"
  line L0 (-3.1473, 2.9487) -> (-4.6629, 3.8237)
  line L1 (-4.6629, 3.8237) -> (-5.6429, 2.1263)
  line L2 (-5.6429, 2.1263) -> (-4.1273, 1.2513)
  line L3 (-4.1273, 1.2513) -> (-3.1473, 2.9487)
extrude "线圈外包络'''''" add sketch "Sketch1 (26)" along normal blind 5.16 from surface at 1.72 separate body makes body 26 in component "08_coil_06_Cn Cn 32匝绕组包络"
sketch "Sketch2 (11)" plane through (0, 0, 0) normal (0, 0, 1) x (1, 0, 0) in component "08_coil_06_Cn Cn 32匝绕组包络"
  line L0 (-3.3786, 2.528) -> (-4.9115, 3.413)
  line L1 (-4.9115, 3.413) -> (-5.4115, 2.547)
  line L2 (-5.4115, 2.547) -> (-3.8786, 1.662)
  line L3 (-3.8786, 1.662) -> (-3.3786, 2.528)
extrude "绕组齿间通道'''''" cut sketch "Sketch2 (11)" along normal blind 4.2 from surface at 2.2 bodies 26 in component "08_coil_06_Cn Cn 32匝绕组包络"
sketch "Sketch1 (27)" plane through (0, 0, 0) normal (0, 0, 1) x (1, 0, 0) in component "08_coil_07_An An 32匝绕组包络"
  line L0 (-4.2, 0.98) -> (-5.95, 0.98)
  line L1 (-5.95, 0.98) -> (-5.95, -0.98)
  line L2 (-5.95, -0.98) -> (-4.2, -0.98)
  line L3 (-4.2, -0.98) -> (-4.2, 0.98)
extrude "线圈外包络''''''" add sketch "Sketch1 (27)" along normal blind 5.16 from surface at 1.72 separate body makes body 27 in component "08_coil_07_An An 32匝绕组包络"
sketch "Sketch2 (12)" plane through (0, 0, 0) normal (0, 0, 1) x (1, 0, 0) in component "08_coil_07_An An 32匝绕组包络"
  line L0 (-4.19, 0.5) -> (-5.96, 0.5)
  line L1 (-5.96, 0.5) -> (-5.96, -0.5)
  line L2 (-5.96, -0.5) -> (-4.19, -0.5)
  line L3 (-4.19, -0.5) -> (-4.19, 0.5)
extrude "绕组齿间通道''''''" cut sketch "Sketch2 (12)" along normal blind 4.2 from surface at 2.2 bodies 27 in component "08_coil_07_An An 32匝绕组包络"
sketch "Sketch1 (28)" plane through (0, 0, 0) normal (0, 0, 1) x (1, 0, 0) in component "08_coil_08_Ap Ap 32匝绕组包络"
  line L0 (-4.1273, -1.2513) -> (-5.6429, -2.1263)
  line L1 (-5.6429, -2.1263) -> (-4.6629, -3.8237)
  line L2 (-4.6629, -3.8237) -> (-3.1473, -2.9487)
  line L3 (-3.1473, -2.9487) -> (-4.1273, -1.2513)
extrude "线圈外包络'''''''" add sketch "Sketch1 (28)" along normal blind 5.16 from surface at 1.72 separate body makes body 28 in component "08_coil_08_Ap Ap 32匝绕组包络"
sketch "Sketch2 (13)" plane through (0, 0, 0) normal (0, 0, 1) x (1, 0, 0) in component "08_coil_08_Ap Ap 32匝绕组包络"
  line L0 (-3.8786, -1.662) -> (-5.4115, -2.547)
  line L1 (-5.4115, -2.547) -> (-4.9115, -3.413)
  line L2 (-4.9115, -3.413) -> (-3.3786, -2.528)
  line L3 (-3.3786, -2.528) -> (-3.8786, -1.662)
extrude "绕组齿间通道'''''''" cut sketch "Sketch2 (13)" along normal blind 4.2 from surface at 2.2 bodies 28 in component "08_coil_08_Ap Ap 32匝绕组包络"
sketch "Sketch1 (29)" plane through (0, 0, 0) normal (0, 0, 1) x (1, 0, 0) in component "08_coil_09_Bp Bp 32匝绕组包络"
  line L0 (-2.9487, -3.1473) -> (-3.8237, -4.6629)
  line L1 (-3.8237, -4.6629) -> (-2.1263, -5.6429)
  line L2 (-2.1263, -5.6429) -> (-1.2513, -4.1273)
  line L3 (-1.2513, -4.1273) -> (-2.9487, -3.1473)
extrude "线圈外包络''''''''" add sketch "Sketch1 (29)" along normal blind 5.16 from surface at 1.72 separate body makes body 29 in component "08_coil_09_Bp Bp 32匝绕组包络"
sketch "Sketch2 (14)" plane through (0, 0, 0) normal (0, 0, 1) x (1, 0, 0) in component "08_coil_09_Bp Bp 32匝绕组包络"
  line L0 (-2.528, -3.3786) -> (-3.413, -4.9115)
  line L1 (-3.413, -4.9115) -> (-2.547, -5.4115)
  line L2 (-2.547, -5.4115) -> (-1.662, -3.8786)
  line L3 (-1.662, -3.8786) -> (-2.528, -3.3786)
extrude "绕组齿间通道''''''''" cut sketch "Sketch2 (14)" along normal blind 4.2 from surface at 2.2 bodies 29 in component "08_coil_09_Bp Bp 32匝绕组包络"
sketch "Sketch1 (30)" plane through (0, 0, 0) normal (0, 0, 1) x (1, 0, 0) in component "08_coil_10_Bn Bn 32匝绕组包络"
  line L0 (-0.98, -4.2) -> (-0.98, -5.95)
  line L1 (-0.98, -5.95) -> (0.98, -5.95)
  line L2 (0.98, -5.95) -> (0.98, -4.2)
  line L3 (0.98, -4.2) -> (-0.98, -4.2)
extrude "线圈外包络'''''''''" add sketch "Sketch1 (30)" along normal blind 5.16 from surface at 1.72 separate body makes body 30 in component "08_coil_10_Bn Bn 32匝绕组包络"
sketch "Sketch2 (15)" plane through (0, 0, 0) normal (0, 0, 1) x (1, 0, 0) in component "08_coil_10_Bn Bn 32匝绕组包络"
  line L0 (-0.5, -4.19) -> (-0.5, -5.96)
  line L1 (-0.5, -5.96) -> (0.5, -5.96)
  line L2 (0.5, -5.96) -> (0.5, -4.19)
  line L3 (0.5, -4.19) -> (-0.5, -4.19)
extrude "绕组齿间通道'''''''''" cut sketch "Sketch2 (15)" along normal blind 4.2 from surface at 2.2 bodies 30 in component "08_coil_10_Bn Bn 32匝绕组包络"
sketch "Sketch1 (31)" plane through (0, 0, 0) normal (0, 0, 1) x (1, 0, 0) in component "08_coil_11_Cn Cn 32匝绕组包络"
  line L0 (1.2513, -4.1273) -> (2.1263, -5.6429)
  line L1 (2.1263, -5.6429) -> (3.8237, -4.6629)
  line L2 (3.8237, -4.6629) -> (2.9487, -3.1473)
  line L3 (2.9487, -3.1473) -> (1.2513, -4.1273)
extrude "线圈外包络''''''''''" add sketch "Sketch1 (31)" along normal blind 5.16 from surface at 1.72 separate body makes body 31 in component "08_coil_11_Cn Cn 32匝绕组包络"
sketch "Sketch2 (16)" plane through (0, 0, 0) normal (0, 0, 1) x (1, 0, 0) in component "08_coil_11_Cn Cn 32匝绕组包络"
  line L0 (1.662, -3.8786) -> (2.547, -5.4115)
  line L1 (2.547, -5.4115) -> (3.413, -4.9115)
  line L2 (3.413, -4.9115) -> (2.528, -3.3786)
  line L3 (2.528, -3.3786) -> (1.662, -3.8786)
extrude "绕组齿间通道''''''''''" cut sketch "Sketch2 (16)" along normal blind 4.2 from surface at 2.2 bodies 31 in component "08_coil_11_Cn Cn 32匝绕组包络"
sketch "Sketch1 (32)" plane through (0, 0, 0) normal (0, 0, 1) x (1, 0, 0) in component "08_coil_12_Cp Cp 32匝绕组包络"
  line L0 (3.1473, -2.9487) -> (4.6629, -3.8237)
  line L1 (4.6629, -3.8237) -> (5.6429, -2.1263)
  line L2 (5.6429, -2.1263) -> (4.1273, -1.2513)
  line L3 (4.1273, -1.2513) -> (3.1473, -2.9487)
extrude "线圈外包络'''''''''''" add sketch "Sketch1 (32)" along normal blind 5.16 from surface at 1.72 separate body makes body 32 in component "08_coil_12_Cp Cp 32匝绕组包络"
sketch "Sketch2 (17)" plane through (0, 0, 0) normal (0, 0, 1) x (1, 0, 0) in component "08_coil_12_Cp Cp 32匝绕组包络"
  line L0 (3.3786, -2.528) -> (4.9115, -3.413)
  line L1 (4.9115, -3.413) -> (5.4115, -2.547)
  line L2 (5.4115, -2.547) -> (3.8786, -1.662)
  line L3 (3.8786, -1.662) -> (3.3786, -2.528)
extrude "绕组齿间通道'''''''''''" cut sketch "Sketch2 (17)" along normal blind 4.2 from surface at 2.2 bodies 32 in component "08_coil_12_Cp Cp 32匝绕组包络"
sketch "Sketch1 (33)" plane through (0, 0, 0) normal (0, 0, 1) x (1, 0, 0) in component "09_bearing_1 MR52ZZ 轴承包络"
  circle A0 centre (0, 0) radius 2.5
  circle A1 centre (0, 0) radius 1
  dimension "d332" = 5
  dimension "d333" = 2
  measures "d332" diameter of A0
  measures "d333" diameter of A1
extrude "轴承 D2xD5x2.5 包络" add sketch "Sketch1 (33)" along normal blind 2.5 from surface at 2.7 separate body makes body 33 in component "09_bearing_1 MR52ZZ 轴承包络"
sketch "Sketch1 (34)" plane through (0, 0, 0) normal (0, 0, 1) x (1, 0, 0) in component "09_bearing_2 MR52ZZ 轴承包络"
  circle A0 centre (0, 0) radius 2.5
  circle A1 centre (0, 0) radius 1
  dimension "d337" = 5
  dimension "d338" = 2
  measures "d337" diameter of A0
  measures "d338" diameter of A1
extrude "轴承 D2xD5x2.5 包络'" add sketch "Sketch1 (34)" along normal blind 2.5 from surface at 5.3 separate body makes body 34 in component "09_bearing_2 MR52ZZ 轴承包络"
sketch "Sketch1 (35)" plane through (0, 0, 0) normal (0, 0, 1) x (1, 0, 0) in component "10_inner_spacer 内圈隔垫"
  circle A0 centre (0, 0) radius 1.3
  circle A1 centre (0, 0) radius 1
  dimension "d342" = 2.6
  dimension "d343" = 2
  measures "d342" diameter of A0
  measures "d343" diameter of A1
extrude "内隔垫 H0.10" add sketch "Sketch1 (35)" along normal blind 0.1 from surface at 5.2 separate body makes body 35 in component "10_inner_spacer 内圈隔垫"
sketch "Sketch1 (36)" plane through (0, 0, 0) normal (0, 0, 1) x (1, 0, 0) in component "11_lower_outer_retainer 轴承外圈挡环"
  circle A0 centre (0, 0) radius 2.5
  circle A1 centre (0, 0) radius 2.25
  dimension "d347" = 5
  dimension "d348" = 4.5
  measures "d347" diameter of A0
  measures "d348" diameter of A1
extrude "外圈挡环 H0.20" add sketch "Sketch1 (36)" along normal blind 0.2 from surface at 2.5 separate body makes body 36 in component "11_lower_outer_retainer 轴承外圈挡环"
sketch "Sketch1 (37)" plane through (0, 0, 0) normal (0, 0, 1) x (1, 0, 0) in component "12_upper_outer_retainer 轴承外圈挡环"
  circle A0 centre (0, 0) radius 2.5
  circle A1 centre (0, 0) radius 2.25
  dimension "d352" = 5
  dimension "d353" = 4.5
  measures "d352" diameter of A0
  measures "d353" diameter of A1
extrude "外圈挡环 H0.20'" add sketch "Sketch1 (37)" along normal blind 0.2 from surface at 7.8 separate body makes body 37 in component "12_upper_outer_retainer 轴承外圈挡环"
sketch "Sketch1 (38)" plane through (0, 0, 0) normal (0, 0, 1) x (1, 0, 0) in component "13_sensor_magnet 两极径向测角磁铁"
  circle A0 centre (0, 0) radius 2
  dimension "d357" = 4
  measures "d357" diameter of A0
extrude "D4x0.5 测角磁铁" add sketch "Sketch1 (38)" along normal blind 0.5 from surface at 1.88 separate body makes body 38 in component "13_sensor_magnet 两极径向测角磁铁"
sketch "Sketch1 (39)" plane through (0, 0, 0) normal (0, 0, 1) x (1, 0, 0) in component "14_sensor_flex 测角刚柔板包络"
  circle A0 centre (0, 0) radius 2.75
  dimension "d361" = 5.5
  measures "d361" diameter of A0
extrude "D5.5 加强区" add sketch "Sketch1 (39)" along normal blind 0.4 separate body makes body 39 in component "14_sensor_flex 测角刚柔板包络"
sketch "Sketch2 (18)" plane through (0, 0, 0) normal (0, 0, 1) x (1, 0, 0) in component "14_sensor_flex 测角刚柔板包络"
  line L0 (0.5657, 0.5657) -> (-4.2426, 5.374)
  line L1 (-4.2426, 5.374) -> (-5.374, 4.2426)
  line L2 (-5.374, 4.2426) -> (-0.5657, -0.5657)
  line L3 (-0.5657, -0.5657) -> (0.5657, 0.5657)
extrude "传感器软排线包络" add sketch "Sketch2 (18)" along normal blind 0.15 bodies 39 in component "14_sensor_flex 测角刚柔板包络"
sketch "Sketch1 (40)" plane through (0, 0, 0) normal (0, 0, 1) x (1, 0, 0) in component "15_MT6701_max_envelope 角度芯片最大包络"
  line L0 (-1.55, -1.55) -> (1.55, -1.55)
  line L1 (1.55, -1.55) -> (1.55, 1.55)
  line L2 (1.55, 1.55) -> (-1.55, 1.55)
  line L3 (-1.55, 1.55) -> (-1.55, -1.55)
extrude "MT6701 QFN16 最大外形" add sketch "Sketch1 (40)" along normal blind 0.8 from surface at 0.45 separate body makes body 40 in component "15_MT6701_max_envelope 角度芯片最大包络"
sketch "Sketch1 (41)" plane through (0, 0, 0) normal (0, 0, 1) x (1, 0, 0) in component "16_sensor_decoupling 0201 去耦包络"
  line L0 (1.65, -0.15) -> (2.25, -0.15)
  line L1 (2.25, -0.15) -> (2.25, 0.15)
  line L2 (2.25, 0.15) -> (1.65, 0.15)
  line L3 (1.65, 0.15) -> (1.65, -0.15)
extrude "100nF 0201 包络" add sketch "Sketch1 (41)" along normal blind 0.3 from surface at 0.45 separate body makes body 41 in component "16_sensor_decoupling 0201 去耦包络"
component "B 固定总成 | STATOR + SENSOR" placed x (1, 0, 0) y (0, 1, 0) z (0, 0, 1) at (0, 0, 0)
component "A 旋转总成 | ROTOR" placed x (1, 0, 0) y (0, 1, 0) z (0, 0, 1) at (0, 0, 0)
component "01_grip_ring POM 防滑外圈" placed x (1, 0, 0) y (0, 1, 0) z (0, 0, 1) at (0, 0, 0) in component "A 旋转总成 | ROTOR"
component "02_rotor_back_iron 低碳钢磁轭" placed x (1, 0, 0) y (0, 1, 0) z (0, 0, 1) at (0, 0, 0) in component "A 旋转总成 | ROTOR"
component "03_rotor_cap 铝端盖" placed x (1, 0, 0) y (0, 1, 0) z (0, 0, 1) at (0, 0, 0) in component "A 旋转总成 | ROTOR"
component "04_rotor_shaft 非磁性精密轴 D2" placed x (1, 0, 0) y (0, 1, 0) z (0, 0, 1) at (0, 0, 0) in component "A 旋转总成 | ROTOR"
component "05_magnet_01_N 弧形磁钢 内侧N极" placed x (1, 0, 0) y (0, 1, 0) z (0, 0, 1) at (0, 0, 0) in component "A 旋转总成 | ROTOR"
component "05_magnet_02_S 弧形磁钢 内侧S极" placed x (1, 0, 0) y (0, 1, 0) z (0, 0, 1) at (0, 0, 0) in component "A 旋转总成 | ROTOR"
component "05_magnet_03_N 弧形磁钢 内侧N极" placed x (1, 0, 0) y (0, 1, 0) z (0, 0, 1) at (0, 0, 0) in component "A 旋转总成 | ROTOR"
component "05_magnet_04_S 弧形磁钢 内侧S极" placed x (1, 0, 0) y (0, 1, 0) z (0, 0, 1) at (0, 0, 0) in component "A 旋转总成 | ROTOR"
component "05_magnet_05_N 弧形磁钢 内侧N极" placed x (1, 0, 0) y (0, 1, 0) z (0, 0, 1) at (0, 0, 0) in component "A 旋转总成 | ROTOR"
component "05_magnet_06_S 弧形磁钢 内侧S极" placed x (1, 0, 0) y (0, 1, 0) z (0, 0, 1) at (0, 0, 0) in component "A 旋转总成 | ROTOR"
component "05_magnet_07_N 弧形磁钢 内侧N极" placed x (1, 0, 0) y (0, 1, 0) z (0, 0, 1) at (0, 0, 0) in component "A 旋转总成 | ROTOR"
component "05_magnet_08_S 弧形磁钢 内侧S极" placed x (1, 0, 0) y (0, 1, 0) z (0, 0, 1) at (0, 0, 0) in component "A 旋转总成 | ROTOR"
component "05_magnet_09_N 弧形磁钢 内侧N极" placed x (1, 0, 0) y (0, 1, 0) z (0, 0, 1) at (0, 0, 0) in component "A 旋转总成 | ROTOR"
component "05_magnet_10_S 弧形磁钢 内侧S极" placed x (1, 0, 0) y (0, 1, 0) z (0, 0, 1) at (0, 0, 0) in component "A 旋转总成 | ROTOR"